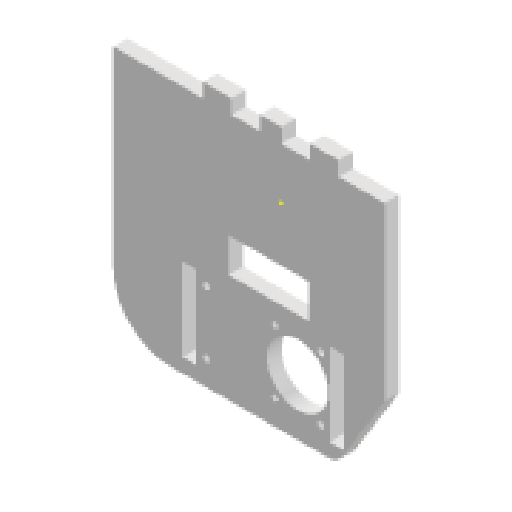
# Autodesk Inventor part: BodySide
Saved by Autodesk Inventor 2025.2 (Build 292293000, 293)
## iProperties
Created: 2025-06-25
Part Number: BodySide
Material: Generic
Document SubType Name: Modeling
Designer: ricoa
Density: 1 g/cm^3
Appearance: Default
Author: ricoa
Autodesk Inventor part; units mm, degrees
ref_plane "YZ Plane" through (0, 0, 0) normal (1, 0, 0) x (0, 1, 0)
ref_plane "XZ Plane" through (0, 0, 0) normal (0, 1, 0) x (-1, 0, 0)
ref_plane "XY Plane" through (0, 0, 0) normal (0, 0, 1) x (1, 0, 0)
sketch "Sketch1" plane through (0, 0, 0) normal (0, 0, 1) x (1, 0, 0)
  line L0 (0, 0) -> (10, 0) projected
  line L1 (-7.5, 5) -> (0, 5) projected
  line L2 (10, 5) -> (20, 5) projected
  line L3 (20, 5) -> (20, 0) projected
  line L4 (20, 0) -> (30, 0) projected
  line L5 (25, -30) -> (25, 0) projected
  line L6 (10, 0) -> (10, 5) projected
  line L7 (0, 5) -> (0, 0) projected
  line L8 (-7.5, 0) -> (-7.5, 5) projected
  line L9 (-17.5, 0) -> (-7.5, 0) projected
  line L10 (-17.5, 5) -> (-17.5, 0) projected
  line L11 (-27.5, 5) -> (-17.5, 5) projected
  line L12 (-27.5, 0) -> (-27.5, 5) projected
  line L13 (-37.5, 0) -> (-27.5, 0) projected
  line L14 (25, -15) -> (0, -15) construction
  line L15 (-7.5, -35) -> (0, -35)
  line L16 (10, -35) -> (20, -35)
  line L17 (20, -35) -> (20, -30)
  line L18 (10, -30) -> (10, -35)
  line L19 (0, -35) -> (0, -30)
  line L20 (-7.5, -30) -> (-7.5, -35)
  line L21 (-17.5, -35) -> (-17.5, -30)
  line L22 (-27.5, -35) -> (-17.5, -35)
  line L23 (-27.5, -30) -> (-27.5, -35)
  line L24 (20, -30) -> (10, -30)
  line L25 (0, -30) -> (-7.5, -30)
  line L26 (-17.5, -30) -> (-27.5, -30)
  line L27 (-37.5, 0) -> (-37.5, -64)
  line L28 (25, -30) -> (25, -35)
  line L29 (17, -35) -> (17, -69) construction
  line L30 (17, -52) -> (30, -52) construction
  line L31 (30, -35) -> (30, -50.5804)
  line L32 (-32.5, -69) -> (16.7114, -69)
  line L33 (29.254, -53.2078) -> (20.9654, -66.6275)
  arc A0 (29.254, -53.2078) -> (30, -50.5804) centre (25, -50.5804) ccw
  arc A1 (16.7114, -69) -> (20.9654, -66.6275) centre (16.7114, -64) ccw
  arc A2 (-37.5, -64) -> (-32.5, -69) centre (-32.5, -64) ccw
  line L34 (25, -35) -> (30, -35)
  line L35 (10, -35) -> (20, -35)
  line L36 (30, -35) -> (25, -35)
  line L37 (20, -35) -> (17, -35)
  line L38 (-27.5, -35) -> (-17.5, -35)
  line L39 (-7.5, -35) -> (0, -35)
  line L40 (25, -35) -> (20, -35) construction
  line L41 (10, -35) -> (0, -35) construction
  line L42 (-7.5, -35) -> (-17.5, -35) construction
  line L43 (-27.5, -35) -> (-37.5, -35) construction
  point P0 (-37.5, -69)
  point P1 (19.5, -69)
  dimension "d1" = 13
  dimension "d2" = 34
  dimension "d3" = 57
  dimension "d4" = 17
  dimension "d5" = 5
  dimension "d6" = 5
  constraints: 60 end point, 12 symmetric about line, 9 point on line, 7 horizontal, 7 perpendicular, 6 point on circle, 6 tangent, 4 collinear, 3 centre point, 2 midpoint, 2 vertical, 1 equal radius
  measures "d1" distance of L31.start L29.start
  measures "d2" distance of L29.start L29.end
  measures "d3" distance of point (-37.5, -69) point (19.5, -69)
  measures "d4" distance of L31.start L30.end
  measures "d5" radius of A0
  measures "d6" radius of A2
extrude "Extrusion1" add sketch "Sketch1" along normal blind 5 contours L0 L6 L2 L3 L4 L5 L28 L34 L31 A0 L33 A1 L32 A2 L27 L13 L12 L11 L10 L9 L8 L1 L7 | L20 L25 L19 L15 | L18 L24 L17 L16 | L22 L23 L26 L21
sketch "Sketch2" plane through (0, 0, 5) normal (0, 0, 1) x (1, 0, 0)
  circle A0 centre (5.75, -49.25) radius 9.75 construction
  circle A1 centre (13.75, -60.25) radius 2 construction
  circle A2 centre (-26.25, -60.25) radius 2.5 construction
  circle A3 centre (-26.25, -38.25) radius 2.5 construction
  circle A4 centre (13.75, -38.25) radius 2.5 construction
  circle A5 centre (-2.25, -60.25) radius 1
  circle A6 centre (-2.25, -38.25) radius 1
  circle A7 centre (5.75, -49.25) radius 10.75
  circle A8 centre (13.75, -38.25) radius 1.25
  circle A9 centre (13.75, -60.25) radius 1.25
  circle A10 centre (-26.25, -60.25) radius 1.25
  circle A11 centre (-26.25, -38.25) radius 1.25
  point P0 (0, 0)
extrude "Extrusion2" cut sketch "Sketch2" against normal blind 5
sketch "Sketch6" plane through (0, 0, 5) normal (0, 0, 1) x (1, 0, 0)
  point P0 (0, 0)
sketch "Sketch7" plane through (0, 0, 5) normal (0, 0, 1) x (1, 0, 0)
  line L0 (36.0989, 0) -> (36.0989, 5) projected
  line L1 (-58.9011, 0) -> (-58.9011, 5) projected
  line L2 (36.0989, 5) -> (36.0989, 23)
  line L3 (36.0989, 23) -> (-58.9011, 23)
  line L4 (-58.9011, 23) -> (-58.9011, 5)
  circle A0 centre (-26.25, -60.25) radius 1.25 projected
  circle A1 centre (-26.25, -38.25) radius 1.25 projected
  circle A2 centre (-2.25, -60.25) radius 1 projected
  circle A3 centre (13.75, -60.25) radius 1.25 projected
  circle A4 centre (13.75, -38.25) radius 1.25 projected
  circle A5 centre (-2.25, -38.25) radius 1 projected
  circle A6 centre (5.75, -49.25) radius 10.75 projected
  line L5 (20, 5) -> (10, 5) projected
  line L6 (10, 5) -> (10, 0) projected
  line L7 (10, 0) -> (0, 0) projected
  line L8 (0, 0) -> (0, 5) projected
  line L9 (0, 5) -> (-7.5, 5) projected
  line L10 (-7.5, 5) -> (-7.5, 0) projected
  line L11 (-7.5, 0) -> (-17.5, 0) projected
  line L12 (-17.5, 0) -> (-17.5, 5) projected
  line L13 (-17.5, 5) -> (-27.5, 5) projected
  line L14 (-27.5, 5) -> (-27.5, 0) projected
  line L15 (-27.5, 0) -> (-37.5, 0) projected
  line L16 (-37.5, 0) -> (-37.5, -64) projected
  arc A7 (-37.5, -64) -> (-32.5, -69) centre (-32.5, -64) ccw projected
  line L17 (-32.5, -69) -> (16.7114, -69) projected
  arc A8 (16.7114, -69) -> (20.9654, -66.6275) centre (16.7114, -64) ccw projected
  line L18 (20.9654, -66.6275) -> (29.254, -53.2078) projected
  arc A9 (29.254, -53.2078) -> (30, -50.5804) centre (25, -50.5804) ccw projected
  line L19 (30, -50.5804) -> (30, -35) projected
  line L20 (30, -35) -> (25, -35) projected
  line L21 (25, -35) -> (25, 0) projected
  line L22 (25, 0) -> (20, 0) projected
  line L23 (20, 0) -> (20, 5) projected
  line L24 (20, 23) -> (20, 18)
  line L25 (20, 18) -> (36.0989, 18)
  line L26 (10, 18) -> (0, 18)
  line L27 (0, 18) -> (0, 23)
  line L28 (10, 18) -> (10, 23)
  line L29 (-7.5, 18) -> (-7.5, 23)
  line L30 (-7.5, 18) -> (-17.5, 18)
  line L31 (-17.5, 18) -> (-17.5, 23)
  line L32 (-27.5, 18) -> (-58.9011, 18)
  line L33 (-27.5, 18) -> (-27.5, 23)
  line L34 (36.0989, 0) -> (36.0989, -35)
  line L35 (-58.9011, 0) -> (-58.9011, -49)
  line L36 (-38.9011, -69) -> (-32.5, -69)
  arc A10 (-58.9011, -49) -> (-38.9011, -69) centre (-38.9011, -49) ccw
  line L37 (20.9654, -66.6275) -> (33.6827, -46.0375)
  line L38 (33.6827, -46.0375) -> (36.0989, -42.1255)
  line L39 (36.0989, -42.1255) -> (36.0989, -35)
  dimension "d46" = 18
  dimension "d47" = 5
  dimension "d48" = 20
  constraints: 38 end point, 16 point on line, 8 perpendicular, 4 vertical, 3 tangent, 2 point on circle, 1 centre point, 1 collinear
  measures "d46" distance of L0.end L2.end
  measures "d47" distance of L24.start L24.end
  measures "d48" radius of A10
extrude "Extrusion6" add sketch "Sketch7" against normal blind 5 contours L34 L39 L38 L37 A9 L19 L20 L21 L22 L23 L5 L6 L7 L8 L9 L10 L11 L12 L13 L14 L15 L16 A7 L36 A10 L35 L1 L4 L32 L33 L3 L31 L30 L29 L27 L26 L28 L24 L25 L2 L0
sketch "Sketch8" plane through (0, 0, 5) normal (0, 0, 1) x (1, 0, 0)
  line L0 (-34.6511, -64) -> (-34.6511, -35) projected
  line L1 (-34.6511, -35) -> (-29.6511, -35) projected
  line L2 (-29.6511, -64) -> (-29.6511, -35) projected
  line L3 (-34.6511, -64) -> (-29.6511, -64) projected
  line L4 (16.8489, -64) -> (16.8489, -35) projected
  line L5 (16.8489, -35) -> (21.8489, -35) projected
  line L6 (21.8489, -64) -> (21.8489, -35) projected
  line L7 (16.8489, -64) -> (21.8489, -64) projected
  point P0 (0, 0)
extrude "Extrusion7" cut sketch "Sketch8" against normal blind 5
sketch "Sketch9" plane through (0, 0, 5) normal (0, 0, 1) x (1, 0, 0)
  line L0 (-34.6511, -35) -> (-29.6511, -35) projected
  line L1 (-34.6511, -35) -> (-34.6511, -25)
  line L2 (-34.6511, -25) -> (21.8489, -25) construction
  line L3 (21.8489, -64) -> (21.8489, -35) projected
  line L4 (21.8489, -25) -> (21.8489, -10)
  line L5 (21.8489, -10) -> (-34.6511, -10)
  line L6 (-34.6511, -10) -> (-34.6511, -25)
  line L7 (9.5989, -19) -> (-18.4011, -19)
  line L8 (-18.4011, -19) -> (-18.4011, -31)
  line L9 (-18.4011, -31) -> (9.5989, -31)
  line L10 (9.5989, -31) -> (9.5989, -19)
  point P0 (0, 0)
  point P1 (-6.4011, -25)
  dimension "d53" = 10
  dimension "d54" = 15
  dimension "d59" = 12
  dimension "d60" = 28
  constraints: 18 end point, 4 perpendicular, 2 parallel, 1 collinear, 1 midpoint, 1 point on line, 1 vertical
  measures "d53" distance of L0.start L1.end
  measures "d54" distance of L2.end L4.end
  measures "d59" distance between parallel lines of L7 L9
  measures "d60" distance between parallel lines of L8 L10
extrude "Extrusion8" cut sketch "Sketch9" against normal blind 5
body "Solid1"
